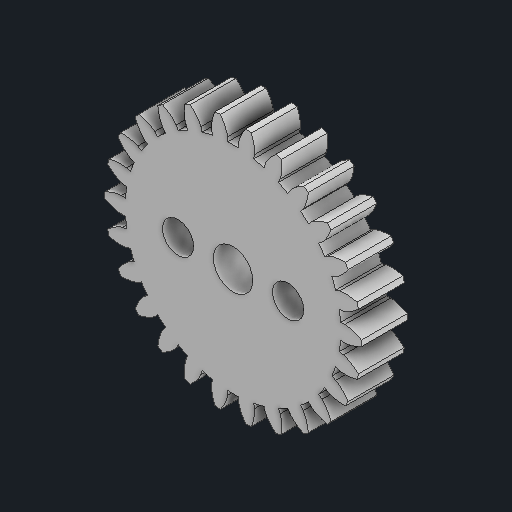
# Autodesk Inventor part: P2-02 Left driven gear 26 teeth
Saved by Autodesk Inventor 2027.1 (Build 311270010, 270A)
## iProperties
Created: 2026-10-21
Part Number: P2-02 Left driven gear 26 teeth
Material: Generic
Document SubType Name: Modeling
Designer: anshi
Mass: 2.32576 g
Surface Area: 20.344 cm^2
Volume: 2.32576 cm^3
Density: 1 g/cm^3
Appearance: Default
Author: anshi
Autodesk Inventor part; units mm, degrees
ref_plane "YZ Plane" through (0, 0, 0) normal (1, 0, 0) x (0, 1, 0)
ref_plane "XZ Plane" through (0, 0, 0) normal (0, 1, 0) x (-1, 0, 0)
ref_plane "XY Plane" through (0, 0, 0) normal (0, 0, 1) x (1, 0, 0)
sketch "Dimensioned base profile" plane through (0, 0, 0) normal (0, 0, 1) x (1, 0, 0)
  line L0 (11.72, -0.8391) -> (12.1848, -0.8724)
  spline S0 degree 4 poles (12.1848, -0.8724) (12.1929, -0.8729) (12.2327, -0.8739) (12.2995, -0.8712) (12.4119, -0.8604) (12.5297, -0.8434) (12.6734, -0.8161) (12.8414, -0.7759) (13.033, -0.7206) (13.338, -0.6171) (13.6097, -0.5031) (13.8321, -0.3954) (13.9966, -0.308) knots 0 0 0 0 0 0.103858 0.165063 0.236355 0.316365 0.404189 0.499163 0.600773 0.708602 1 1 1 1 1
  arc A0 (13.9966, -0.308) -> (13.9966, 0.308) centre (0, 0) ccw
  spline S1 degree 4 poles (13.9966, 0.308) (13.8319, 0.3954) (13.6094, 0.503) (13.3375, 0.6169) (13.0324, 0.7203) (12.8406, 0.7756) (12.6726, 0.8157) (12.5289, 0.8431) (12.4112, 0.8601) (12.299, 0.871) (12.2325, 0.8737) (12.1928, 0.8729) (12.1848, 0.8724) knots 0 0 0 0 0 0.291573 0.399464 0.501128 0.596147 0.684003 0.76403 0.835317 0.896484 1 1 1 1 1
  line L1 (12.1848, 0.8724) -> (11.72, 0.8391)
  arc A1 (11.72, 0.8391) -> (11.5802, 1.9901) centre (0, 0) ccw
  line L2 (11.5802, 1.9901) -> (12.0395, 2.069)
  spline S2 degree 4 poles (12.0395, 2.069) (12.0476, 2.0703) (12.0864, 2.079) (12.1506, 2.0976) (12.2571, 2.135) (12.3674, 2.1797) (12.5004, 2.2407) (12.6539, 2.3199) (12.8267, 2.4194) (13.0981, 2.5929) (13.3346, 2.7686) (13.5248, 2.9263) (13.6636, 3.0505) knots 0 0 0 0 0 0.103855 0.165058 0.23635 0.316361 0.404186 0.499161 0.600771 0.708601 1 1 1 1 1
  arc A2 (13.6636, 3.0505) -> (13.5162, 3.6487) centre (0, 0) ccw
  spline S3 degree 4 poles (13.5162, 3.6487) (13.3348, 3.6939) (13.0921, 3.7449) (12.8, 3.7902) (12.4781, 3.8174) (12.2784, 3.8251) (12.1055, 3.8238) (11.9595, 3.816) (11.8415, 3.8045) (11.7309, 3.7884) (11.6666, 3.7754) (11.6289, 3.7653) (11.622, 3.763) knots 0 0 0 0 0 0.29244 0.40063 0.502549 0.597769 0.685759 0.765834 0.837054 0.897986 1 1 1 1 1
  line L3 (11.622, 3.763) -> (11.1786, 3.6195)
  arc A3 (11.1786, 3.6195) -> (10.7675, 4.7036) centre (0, 0) ccw
  line L4 (10.7675, 4.7036) -> (11.1945, 4.8901)
  spline S4 degree 4 poles (11.1945, 4.8901) (11.202, 4.8933) (11.2377, 4.911) (11.2956, 4.9444) (11.3901, 5.0061) (11.4864, 5.0759) (11.601, 5.167) (11.7311, 5.2806) (11.8751, 5.4186) (12.097, 5.6521) (12.2846, 5.8792) (12.4315, 6.0779) (12.5365, 6.2318) knots 0 0 0 0 0 0.103853 0.165057 0.236348 0.316359 0.404183 0.499157 0.600768 0.708598 1 1 1 1 1
  arc A4 (12.5365, 6.2318) -> (12.2502, 6.7773) centre (0, 0) ccw
  spline S5 degree 4 poles (12.2502, 6.7773) (12.0633, 6.7779) (11.8155, 6.7695) (11.521, 6.7437) (11.202, 6.6932) (11.0062, 6.6529) (10.8386, 6.6104) (10.6987, 6.5678) (10.5869, 6.5284) (10.4833, 6.4861) (10.424, 6.458) (10.3898, 6.4391) (10.3837, 6.435) knots 0 0 0 0 0 0.292402 0.400578 0.502484 0.597694 0.685676 0.765748 0.836972 0.89792 1 1 1 1 1
  line L5 (10.3837, 6.435) -> (9.9876, 6.1895)
  arc A5 (9.9876, 6.1895) -> (9.329, 7.1437) centre (0, 0) ccw
  line L6 (9.329, 7.1437) -> (9.699, 7.427)
  spline S6 degree 4 poles (9.699, 7.427) (9.7055, 7.4319) (9.7358, 7.4576) (9.784, 7.5039) (9.861, 7.5865) (9.9379, 7.6773) (10.0273, 7.7932) (10.1264, 7.9346) (10.2332, 8.1031) (10.3928, 8.3828) (10.5206, 8.6483) (10.6157, 8.8764) (10.6809, 9.0509) knots 0 0 0 0 0 0.103839 0.165041 0.236333 0.316345 0.40417 0.499146 0.600759 0.708592 1 1 1 1 1
  arc A6 (10.6809, 9.0509) -> (10.2724, 9.512) centre (0, 0) ccw
  spline S7 degree 4 poles (10.2724, 9.512) (10.0908, 9.4678) (9.8525, 9.4003) (9.573, 9.3046) (9.2755, 9.1792) (9.0952, 9.0932) (8.9428, 9.0117) (8.8171, 8.9369) (8.7179, 8.8719) (8.6273, 8.8061) (8.5762, 8.7647) (8.5473, 8.7382) (8.542, 8.733) knots 0 0 0 0 0 0.292256 0.400384 0.502252 0.597434 0.685401 0.765472 0.836714 0.897704 1 1 1 1 1
  line L7 (8.542, 8.733) -> (8.2161, 8.3999)
  arc A7 (8.2161, 8.3999) -> (7.3483, 9.1687) centre (0, 0) ccw
  line L8 (7.3483, 9.1687) -> (7.6397, 9.5323)
  spline S8 degree 4 poles (7.6397, 9.5323) (7.6448, 9.5387) (7.6682, 9.5709) (7.7039, 9.6274) (7.7589, 9.726) (7.8118, 9.8326) (7.8709, 9.9664) (7.9333, 10.1275) (7.9966, 10.3166) (8.0847, 10.6264) (8.1452, 10.9148) (8.1829, 11.1589) (8.2045, 11.344) knots 0 0 0 0 0 0.10386 0.165065 0.236357 0.316368 0.404192 0.499165 0.600774 0.708603 1 1 1 1 1
  arc A8 (8.2045, 11.344) -> (7.6975, 11.694) centre (0, 0) ccw
  spline S9 degree 4 poles (7.6975, 11.694) (7.5314, 11.6077) (7.3155, 11.4853) (7.0663, 11.3257) (6.8069, 11.1329) (6.6521, 11.0063) (6.5234, 10.8908) (6.4193, 10.7881) (6.3388, 10.7012) (6.2671, 10.6156) (6.2279, 10.563) (6.2071, 10.5302) (6.2038, 10.5235) knots 0 0 0 0 0 0.292519 0.400726 0.502651 0.597866 0.685837 0.765878 0.83705 0.897921 1 1 1 1 1
  line L9 (6.2038, 10.5235) -> (5.9672, 10.122)
  arc A9 (5.9672, 10.122) -> (4.9405, 10.6608) centre (0, 0) ccw
  line L10 (4.9405, 10.6608) -> (5.1365, 11.0837)
  spline S10 degree 4 poles (5.1365, 11.0837) (5.14, 11.091) (5.1549, 11.1279) (5.1761, 11.1913) (5.2059, 11.3002) (5.2317, 11.4163) (5.2571, 11.5605) (5.2791, 11.7317) (5.2954, 11.9305) (5.3067, 12.2524) (5.2965, 12.5469) (5.2747, 12.793) (5.2513, 12.9778) knots 0 0 0 0 0 0.103856 0.16506 0.236352 0.316363 0.404186 0.499161 0.60077 0.7086 1 1 1 1 1
  arc A10 (5.2513, 12.9778) -> (4.6753, 13.1963) centre (0, 0) ccw
  spline S11 degree 4 poles (4.6753, 13.1963) (4.5348, 13.0731) (4.3548, 12.9029) (4.1513, 12.6887) (3.9458, 12.4397) (3.8259, 12.2799) (3.7287, 12.137) (3.6521, 12.0123) (3.5946, 11.9085) (3.5452, 11.8079) (3.5195, 11.747) (3.5067, 11.7098) (3.5051, 11.7023) knots 0 0 0 0 0 0.292105 0.400173 0.501984 0.597113 0.685035 0.765074 0.836305 0.897322 1 1 1 1 1
  line L11 (3.5051, 11.7023) -> (3.3714, 11.2559)
  arc A11 (3.3714, 11.2559) -> (2.2457, 11.5334) centre (0, 0) ccw
  line L12 (2.2457, 11.5334) -> (2.3347, 11.9908)
  spline S12 degree 4 poles (2.3347, 11.9908) (2.3363, 11.9988) (2.342, 12.0382) (2.3474, 12.1048) (2.3502, 12.2177) (2.3475, 12.3366) (2.3377, 12.4826) (2.318, 12.6542) (2.2863, 12.8511) (2.2203, 13.1664) (2.1399, 13.4498) (2.0598, 13.6836) (1.9929, 13.8574) knots 0 0 0 0 0 0.103856 0.16506 0.236352 0.316364 0.404188 0.499162 0.600772 0.708602 1 1 1 1 1
  arc A12 (1.9929, 13.8574) -> (1.3813, 13.9317) centre (0, 0) ccw
  spline S13 degree 4 poles (1.3813, 13.9317) (1.2743, 13.7784) (1.1401, 13.57) (0.9936, 13.3133) (0.8535, 13.0223) (0.7753, 12.8384) (0.715, 12.6764) (0.6705, 12.5371) (0.6396, 12.4225) (0.6158, 12.3131) (0.6056, 12.2478) (0.6024, 12.2088) (0.6027, 12.2011) knots 0 0 0 0 0 0.292181 0.400272 0.502099 0.597236 0.685158 0.765186 0.836392 0.89737 1 1 1 1 1
  line L13 (0.6027, 12.2011) -> (0.5797, 11.7357)
  arc A13 (0.5797, 11.7357) -> (-0.5797, 11.7357) centre (0, 0) ccw
  line L14 (-0.5797, 11.7357) -> (-0.6027, 12.2011)
  spline S14 degree 4 poles (-0.6027, 12.2011) (-0.6031, 12.2093) (-0.607, 12.2489) (-0.6177, 12.3148) (-0.642, 12.4251) (-0.6731, 12.5399) (-0.7176, 12.6794) (-0.7777, 12.8413) (-0.8557, 13.0248) (-0.9952, 13.3151) (-1.1411, 13.5711) (-1.2747, 13.7789) (-1.3813, 13.9317) knots 0 0 0 0 0 0.103856 0.165061 0.236354 0.316365 0.40419 0.499164 0.600774 0.708603 1 1 1 1 1
  arc A14 (-1.3813, 13.9317) -> (-1.9929, 13.8574) centre (0, 0) ccw
  spline S15 degree 4 poles (-1.9929, 13.8574) (-2.06, 13.6834) (-2.1402, 13.4495) (-2.2208, 13.1658) (-2.2871, 12.8503) (-2.3189, 12.6533) (-2.3386, 12.4817) (-2.3485, 12.3357) (-2.3511, 12.2168) (-2.3482, 12.1042) (-2.3426, 12.0378) (-2.3367, 11.9986) (-2.3347, 11.9908) knots 0 0 0 0 0 0.291613 0.399514 0.501182 0.596199 0.684048 0.764063 0.835332 0.896479 1 1 1 1 1
  line L15 (-2.3347, 11.9908) -> (-2.2457, 11.5334)
  arc A15 (-2.2457, 11.5334) -> (-3.3714, 11.2559) centre (0, 0) ccw
  line L16 (-3.3714, 11.2559) -> (-3.5051, 11.7023)
  spline S16 degree 4 poles (-3.5051, 11.7023) (-3.5075, 11.7101) (-3.5208, 11.7476) (-3.547, 11.8091) (-3.597, 11.9103) (-3.6546, 12.0144) (-3.7312, 12.1391) (-3.8283, 12.2819) (-3.948, 12.4415) (-4.1529, 12.69) (-4.3557, 12.9036) (-4.5352, 13.0734) (-4.6753, 13.1963) knots 0 0 0 0 0 0.103828 0.165032 0.236326 0.31634 0.404168 0.499146 0.60076 0.708593 1 1 1 1 1
  arc A16 (-4.6753, 13.1963) -> (-5.2513, 12.9778) centre (0, 0) ccw
  spline S17 degree 4 poles (-5.2513, 12.9778) (-5.2747, 12.7929) (-5.2967, 12.5466) (-5.307, 12.252) (-5.2958, 11.93) (-5.2796, 11.7311) (-5.2576, 11.5598) (-5.2322, 11.4156) (-5.2063, 11.2996) (-5.1765, 11.1908) (-5.1552, 11.1276) (-5.1402, 11.0908) (-5.1365, 11.0837) knots 0 0 0 0 0 0.291525 0.399396 0.501039 0.596037 0.683875 0.763887 0.835165 0.896335 1 1 1 1 1
  line L17 (-5.1365, 11.0837) -> (-4.9405, 10.6608)
  arc A17 (-4.9405, 10.6608) -> (-5.9672, 10.122) centre (0, 0) ccw
  line L18 (-5.9672, 10.122) -> (-6.2038, 10.5235)
  spline S18 degree 4 poles (-6.2038, 10.5235) (-6.2081, 10.5303) (-6.23, 10.5636) (-6.2702, 10.6169) (-6.3429, 10.7032) (-6.4238, 10.7904) (-6.528, 10.8931) (-6.6565, 11.0086) (-6.8108, 11.1349) (-7.0692, 11.3272) (-7.3172, 11.4862) (-7.5321, 11.6081) (-7.6975, 11.694) knots 0 0 0 0 0 0.103756 0.164954 0.236249 0.316269 0.404104 0.499092 0.600717 0.708562 1 1 1 1 1
  arc A18 (-7.6975, 11.694) -> (-8.2045, 11.344) centre (0, 0) ccw
  spline S19 degree 4 poles (-8.2045, 11.344) (-8.1829, 11.159) (-8.1452, 10.9148) (-8.0845, 10.6265) (-7.9965, 10.3167) (-7.9331, 10.1276) (-7.8707, 9.9665) (-7.8116, 9.8327) (-7.7587, 9.7261) (-7.7038, 9.6275) (-7.6681, 9.571) (-7.6447, 9.5387) (-7.6397, 9.5323) knots 0 0 0 0 0 0.291401 0.399232 0.500844 0.595821 0.683648 0.763661 0.834955 0.89616 1 1 1 1 1
  line L19 (-7.6397, 9.5323) -> (-7.3483, 9.1687)
  arc A19 (-7.3483, 9.1687) -> (-8.2161, 8.3999) centre (0, 0) ccw
  line L20 (-8.2161, 8.3999) -> (-8.542, 8.733)
  spline S20 degree 4 poles (-8.542, 8.733) (-8.5478, 8.7384) (-8.577, 8.7654) (-8.6288, 8.8074) (-8.7201, 8.8737) (-8.8195, 8.939) (-8.9452, 9.0138) (-9.0976, 9.0952) (-9.2777, 9.181) (-9.5745, 9.3059) (-9.8534, 9.4011) (-10.0913, 9.4682) (-10.2724, 9.512) knots 0 0 0 0 0 0.103609 0.164795 0.236092 0.31612 0.403972 0.498979 0.600626 0.708496 1 1 1 1 1
  arc A20 (-10.2724, 9.512) -> (-10.6809, 9.0509) centre (0, 0) ccw
  spline S21 degree 4 poles (-10.6809, 9.0509) (-10.6154, 8.8764) (-10.5201, 8.6484) (-10.3919, 8.383) (-10.232, 8.1033) (-10.125, 7.9349) (-10.0259, 7.7934) (-9.9364, 7.6776) (-9.8597, 7.5868) (-9.783, 7.5043) (-9.7352, 7.4579) (-9.7049, 7.4322) (-9.699, 7.427) knots 0 0 0 0 0 0.29159 0.399491 0.501165 0.596196 0.684064 0.764102 0.835397 0.896565 1 1 1 1 1
  line L21 (-9.699, 7.427) -> (-9.329, 7.1437)
  arc A21 (-9.329, 7.1437) -> (-9.9876, 6.1895) centre (0, 0) ccw
  line L22 (-9.9876, 6.1895) -> (-10.3837, 6.435)
  spline S22 degree 4 poles (-10.3837, 6.435) (-10.3906, 6.4385) (-10.4254, 6.4575) (-10.4855, 6.4856) (-10.5898, 6.5279) (-10.7019, 6.5674) (-10.8419, 6.61) (-11.0093, 6.6526) (-11.2047, 6.6929) (-11.523, 6.7435) (-11.8167, 6.7694) (-12.0638, 6.7779) (-12.2502, 6.7773) knots 0 0 0 0 0 0.103137 0.164277 0.235571 0.315627 0.403525 0.498595 0.600316 0.708269 1 1 1 1 1
  arc A22 (-12.2502, 6.7773) -> (-12.5365, 6.2318) centre (0, 0) ccw
  spline S23 degree 4 poles (-12.5365, 6.2318) (-12.4309, 6.0779) (-12.2834, 5.8792) (-12.095, 5.652) (-11.8724, 5.4186) (-11.728, 5.2805) (-11.5978, 5.1669) (-11.4833, 5.0759) (-11.3872, 5.0062) (-11.2934, 4.9446) (-11.2365, 4.9113) (-11.2011, 4.8935) (-11.1945, 4.8901) knots 0 0 0 0 0 0.292048 0.40011 0.501925 0.59707 0.68502 0.765098 0.836378 0.89745 1 1 1 1 1
  line L23 (-11.1945, 4.8901) -> (-10.7675, 4.7036)
  arc A23 (-10.7675, 4.7036) -> (-11.1786, 3.6195) centre (0, 0) ccw
  line L24 (-11.1786, 3.6195) -> (-11.622, 3.763)
  spline S24 degree 4 poles (-11.622, 3.763) (-11.6296, 3.7651) (-11.6679, 3.7754) (-11.7331, 3.7884) (-11.8446, 3.8047) (-11.9629, 3.8163) (-12.1091, 3.8241) (-12.2818, 3.8254) (-12.4812, 3.8177) (-12.8022, 3.7904) (-13.0935, 3.7451) (-13.3354, 3.694) (-13.5162, 3.6487) knots 0 0 0 0 0 0.103381 0.164541 0.235833 0.315872 0.403744 0.498781 0.600465 0.708377 1 1 1 1 1
  arc A24 (-13.5162, 3.6487) -> (-13.6636, 3.0505) centre (0, 0) ccw
  spline S25 degree 4 poles (-13.6636, 3.0505) (-13.5235, 2.9264) (-13.3318, 2.7688) (-13.0935, 2.5934) (-12.8205, 2.4201) (-12.6469, 2.3206) (-12.4932, 2.2415) (-12.3601, 2.1805) (-12.2506, 2.1358) (-12.1457, 2.0987) (-12.0839, 2.0799) (-12.0456, 2.0711) (-12.0395, 2.069) knots 0 0 0 0 0 0.29301 0.401412 0.503527 0.598921 0.687053 0.767228 0.838488 0.899369 1 1 1 1 1
  line L25 (-12.0395, 2.069) -> (-11.5802, 1.9901)
  arc A25 (-11.5802, 1.9901) -> (-11.72, 0.8391) centre (0, 0) ccw
  line L26 (-11.72, 0.8391) -> (-12.1848, 0.8724)
  spline S26 degree 4 poles (-12.1848, 0.8724) (-12.1924, 0.872) (-12.232, 0.8727) (-12.2981, 0.8694) (-12.41, 0.8584) (-12.5275, 0.8413) (-12.6713, 0.8139) (-12.8393, 0.7738) (-13.0312, 0.7188) (-13.3366, 0.6157) (-13.6088, 0.5023) (-13.8317, 0.3951) (-13.9966, 0.308) knots 0 0 0 0 0 0.102877 0.163993 0.235287 0.315358 0.403282 0.498387 0.600148 0.708146 1 1 1 1 1
  arc A26 (-13.9966, 0.308) -> (-13.9966, -0.308) centre (0, 0) ccw
  spline S27 degree 4 poles (-13.9966, -0.308) (-13.8317, -0.3957) (-13.6089, -0.5037) (-13.3367, -0.618) (-13.0313, -0.7219) (-12.8394, -0.7774) (-12.6714, -0.8176) (-12.5276, -0.845) (-12.41, -0.8619) (-12.2981, -0.8726) (-12.232, -0.8748) (-12.1924, -0.8738) (-12.1848, -0.8724) knots 0 0 0 0 0 0.291935 0.399947 0.50171 0.596805 0.68471 0.764755 0.836019 0.897109 1 1 1 1 1
  line L27 (-12.1848, -0.8724) -> (-11.72, -0.8391)
  arc A27 (-11.72, -0.8391) -> (-11.5802, -1.9901) centre (0, 0) ccw
  line L28 (-11.5802, -1.9901) -> (-12.0395, -2.069)
  spline S28 degree 4 poles (-12.0395, -2.069) (-12.0456, -2.0682) (-12.0839, -2.0767) (-12.1453, -2.0938) (-12.2499, -2.1304) (-12.3594, -2.1746) (-12.4924, -2.2357) (-12.6462, -2.3151) (-12.8199, -2.4152) (-13.0931, -2.5898) (-13.3316, -2.7667) (-13.5234, -2.9255) (-13.6636, -3.0505) knots 0 0 0 0 0 0.099567 0.1603 0.231502 0.311688 0.399892 0.49541 0.597697 0.706314 1 1 1 1 1
  arc A28 (-13.6636, -3.0505) -> (-13.5162, -3.6487) centre (0, 0) ccw
  spline S29 degree 4 poles (-13.5162, -3.6487) (-13.335, -3.6941) (-13.0927, -3.7454) (-12.8009, -3.7909) (-12.4793, -3.8184) (-12.2797, -3.8262) (-12.1069, -3.825) (-11.9607, -3.8171) (-11.8426, -3.8055) (-11.7316, -3.7892) (-11.6671, -3.776) (-11.6289, -3.7656) (-11.622, -3.763) knots 0 0 0 0 0 0.292124 0.400206 0.502033 0.597182 0.685129 0.765198 0.836462 0.897514 1 1 1 1 1
  line L29 (-11.622, -3.763) -> (-11.1786, -3.6195)
  arc A29 (-11.1786, -3.6195) -> (-10.7675, -4.7036) centre (0, 0) ccw
  line L30 (-10.7675, -4.7036) -> (-11.1945, -4.8901)
  spline S30 degree 4 poles (-11.1945, -4.8901) (-11.1997, -4.8899) (-11.2347, -4.9076) (-11.2888, -4.9379) (-11.3807, -4.998) (-11.4759, -5.0668) (-11.5905, -5.158) (-11.721, -5.272) (-11.8661, -5.411) (-12.0904, -5.6465) (-12.2806, -5.8758) (-12.4297, -6.0764) (-12.5365, -6.2318) knots 0 0 0 0 0 0.097235 0.157742 0.228919 0.309217 0.397635 0.493448 0.596096 0.705127 1 1 1 1 1
  arc A30 (-12.5365, -6.2318) -> (-12.2502, -6.7773) centre (0, 0) ccw
  spline S31 degree 4 poles (-12.2502, -6.7773) (-12.0633, -6.7778) (-11.8155, -6.7693) (-11.5211, -6.7433) (-11.2021, -6.6928) (-11.0063, -6.6524) (-10.8387, -6.6098) (-10.6987, -6.5673) (-10.5869, -6.5278) (-10.4834, -6.4856) (-10.4242, -6.4578) (-10.3897, -6.4387) (-10.3837, -6.435) knots 0 0 0 0 0 0.292473 0.400679 0.502616 0.597858 0.685873 0.765978 0.837236 0.898219 1 1 1 1 1
  line L31 (-10.3837, -6.435) -> (-9.9876, -6.1895)
  arc A31 (-9.9876, -6.1895) -> (-9.329, -7.1437) centre (0, 0) ccw
  line L32 (-9.329, -7.1437) -> (-9.699, -7.427)
  spline S32 degree 4 poles (-9.699, -7.427) (-9.7035, -7.4286) (-9.7332, -7.4541) (-9.7778, -7.4966) (-9.8524, -7.5768) (-9.9283, -7.6664) (-10.0178, -7.7823) (-10.1172, -7.9242) (-10.225, -8.0939) (-10.3868, -8.3761) (-10.517, -8.6442) (-10.6141, -8.8746) (-10.6809, -9.0509) knots 0 0 0 0 0 0.096717 0.157193 0.228382 0.308716 0.39719 0.493071 0.595795 0.704908 1 1 1 1 1
  arc A32 (-10.6809, -9.0509) -> (-10.2724, -9.512) centre (0, 0) ccw
  spline S33 degree 4 poles (-10.2724, -9.512) (-10.0909, -9.4678) (-9.8525, -9.4003) (-9.573, -9.3047) (-9.2756, -9.1793) (-9.0953, -9.0932) (-8.9428, -9.0118) (-8.8171, -8.937) (-8.7179, -8.8719) (-8.6272, -8.8061) (-8.5762, -8.7648) (-8.5472, -8.738) (-8.542, -8.733) knots 0 0 0 0 0 0.292271 0.400408 0.502287 0.597482 0.685466 0.765558 0.836826 0.89785 1 1 1 1 1
  line L33 (-8.542, -8.733) -> (-8.2161, -8.3999)
  arc A33 (-8.2161, -8.3999) -> (-7.3483, -9.1687) centre (0, 0) ccw
  line L34 (-7.3483, -9.1687) -> (-7.6397, -9.5323)
  spline S34 degree 4 poles (-7.6397, -9.5323) (-7.6434, -9.5341) (-7.666, -9.5662) (-7.6985, -9.6169) (-7.7513, -9.7121) (-7.8033, -9.817) (-7.8624, -9.951) (-7.9251, -10.1126) (-7.9894, -10.3034) (-8.0793, -10.6167) (-8.142, -10.9089) (-8.1815, -11.1563) (-8.2045, -11.344) knots 0 0 0 0 0 0.094912 0.155236 0.226419 0.306847 0.395489 0.491597 0.594595 0.70402 1 1 1 1 1
  arc A34 (-8.2045, -11.344) -> (-7.6975, -11.694) centre (0, 0) ccw
  spline S35 degree 4 poles (-7.6975, -11.694) (-7.5319, -11.6074) (-7.3166, -11.4845) (-7.0682, -11.3244) (-6.8095, -11.1312) (-6.655, -11.0044) (-6.5264, -10.8888) (-6.4223, -10.786) (-6.3415, -10.6992) (-6.2694, -10.6138) (-6.2297, -10.562) (-6.2079, -10.5291) (-6.2038, -10.5235) knots 0 0 0 0 0 0.292491 0.400708 0.502659 0.597917 0.685948 0.766067 0.837335 0.898317 1 1 1 1 1
  line L35 (-6.2038, -10.5235) -> (-5.9672, -10.122)
  arc A35 (-5.9672, -10.122) -> (-4.9405, -10.6608) centre (0, 0) ccw
  line L36 (-4.9405, -10.6608) -> (-5.1365, -11.0837)
  spline S36 degree 4 poles (-5.1365, -11.0837) (-5.139, -11.087) (-5.1533, -11.1234) (-5.1725, -11.1812) (-5.2011, -11.2865) (-5.2264, -11.4009) (-5.2518, -11.5452) (-5.274, -11.7171) (-5.2908, -11.9175) (-5.3033, -12.2428) (-5.2944, -12.541) (-5.2738, -12.7904) (-5.2513, -12.9778) knots 0 0 0 0 0 0.095662 0.156062 0.22726 0.30766 0.396238 0.492254 0.595137 0.704425 1 1 1 1 1
  arc A36 (-5.2513, -12.9778) -> (-4.6753, -13.1963) centre (0, 0) ccw
  spline S37 degree 4 poles (-4.6753, -13.1963) (-4.5351, -13.0726) (-4.3554, -12.9018) (-4.1523, -12.6869) (-3.9472, -12.4374) (-3.8275, -12.2773) (-3.7303, -12.1343) (-3.6538, -12.0096) (-3.5962, -11.906) (-3.5466, -11.8058) (-3.5207, -11.746) (-3.5074, -11.7089) (-3.5051, -11.7023) knots 0 0 0 0 0 0.292559 0.400798 0.502766 0.598035 0.686073 0.766193 0.837454 0.898421 1 1 1 1 1
  line L37 (-3.5051, -11.7023) -> (-3.3714, -11.2559)
  arc A37 (-3.3714, -11.2559) -> (-2.2457, -11.5334) centre (0, 0) ccw
  line L38 (-2.2457, -11.5334) -> (-2.3347, -11.9908)
  spline S38 degree 4 poles (-2.3347, -11.9908) (-2.336, -11.9943) (-2.3411, -12.0332) (-2.3456, -12.0931) (-2.3481, -12.2018) (-2.3452, -12.3188) (-2.3353, -12.4649) (-2.3158, -12.6372) (-2.2843, -12.836) (-2.2187, -13.1552) (-2.139, -13.443) (-2.0594, -13.6806) (-1.9929, -13.8574) knots 0 0 0 0 0 0.09468 0.155008 0.226212 0.30667 0.395344 0.491485 0.594514 0.703967 1 1 1 1 1
  arc A38 (-1.9929, -13.8574) -> (-1.3813, -13.9317) centre (0, 0) ccw
  spline S39 degree 4 poles (-1.3813, -13.9317) (-1.2749, -13.7779) (-1.1415, -13.5688) (-0.9959, -13.3114) (-0.8566, -13.0198) (-0.7788, -12.8356) (-0.7187, -12.6734) (-0.6743, -12.534) (-0.6431, -12.4198) (-0.6189, -12.3109) (-0.6078, -12.2469) (-0.6037, -12.2077) (-0.6027, -12.2011) knots 0 0 0 0 0 0.292751 0.40106 0.503092 0.598415 0.686495 0.76664 0.837902 0.898833 1 1 1 1 1
  line L39 (-0.6027, -12.2011) -> (-0.5797, -11.7357)
  arc A39 (-0.5797, -11.7357) -> (0.5797, -11.7357) centre (0, 0) ccw
  line L40 (0.5797, -11.7357) -> (0.6027, -12.2011)
  spline S40 degree 4 poles (0.6027, -12.2011) (0.6039, -12.2051) (0.6081, -12.244) (0.6191, -12.304) (0.6429, -12.4106) (0.674, -12.5237) (0.7185, -12.6632) (0.7785, -12.8257) (0.8564, -13.011) (0.9958, -13.3049) (1.1414, -13.5649) (1.2749, -13.7761) (1.3813, -13.9317) knots 0 0 0 0 0 0.095825 0.156263 0.227488 0.307903 0.396483 0.492487 0.595342 0.704587 1 1 1 1 1
  arc A40 (1.3813, -13.9317) -> (1.9929, -13.8574) centre (0, 0) ccw
  spline S41 degree 4 poles (1.9929, -13.8574) (2.0594, -13.683) (2.139, -13.4485) (2.2189, -13.1642) (2.2844, -12.8483) (2.3159, -12.651) (2.3355, -12.4793) (2.3453, -12.3333) (2.3481, -12.2147) (2.3456, -12.1027) (2.3408, -12.0372) (2.3354, -11.998) (2.3347, -11.9908) knots 0 0 0 0 0 0.292214 0.400336 0.502204 0.597394 0.685378 0.765476 0.836753 0.897793 1 1 1 1 1
  line L41 (2.3347, -11.9908) -> (2.2457, -11.5334)
  arc A41 (2.2457, -11.5334) -> (3.3714, -11.2559) centre (0, 0) ccw
  line L42 (3.3714, -11.2559) -> (3.5051, -11.7023)
  spline S42 degree 4 poles (3.5051, -11.7023) (3.508, -11.7081) (3.5214, -11.7451) (3.5475, -11.8041) (3.597, -11.9038) (3.6546, -12.0071) (3.7312, -12.1319) (3.8283, -12.275) (3.9479, -12.4353) (4.1528, -12.6854) (4.3557, -12.9008) (4.5352, -13.0722) (4.6753, -13.1963) knots 0 0 0 0 0 0.100642 0.161525 0.232786 0.312961 0.401093 0.496486 0.5986 0.706999 1 1 1 1 1
  arc A42 (4.6753, -13.1963) -> (5.2513, -12.9778) centre (0, 0) ccw
  spline S43 degree 4 poles (5.2513, -12.9778) (5.2743, -12.7927) (5.2956, -12.5463) (5.3053, -12.2514) (5.2935, -11.9292) (5.277, -11.7303) (5.2549, -11.559) (5.2295, -11.4148) (5.2038, -11.2989) (5.1744, -11.1904) (5.1538, -11.1275) (5.1391, -11.0908) (5.1365, -11.0837) knots 0 0 0 0 0 0.291886 0.399891 0.501658 0.596764 0.684687 0.764753 0.836039 0.897146 1 1 1 1 1
  line L43 (5.1365, -11.0837) -> (4.9405, -10.6608)
  arc A43 (4.9405, -10.6608) -> (5.9672, -10.122) centre (0, 0) ccw
  line L44 (5.9672, -10.122) -> (6.2038, -10.5235)
  spline S44 degree 4 poles (6.2038, -10.5235) (6.208, -10.5279) (6.2299, -10.5605) (6.2693, -10.611) (6.341, -10.6957) (6.4217, -10.7821) (6.5258, -10.8849) (6.6543, -11.0007) (6.8089, -11.1279) (7.0678, -11.322) (7.3164, -11.483) (7.5317, -11.6067) (7.6975, -11.694) knots 0 0 0 0 0 0.099963 0.160782 0.232039 0.312251 0.400449 0.49593 0.598149 0.706667 1 1 1 1 1
  arc A44 (7.6975, -11.694) -> (8.2045, -11.344) centre (0, 0) ccw
  spline S45 degree 4 poles (8.2045, -11.344) (8.1825, -11.1587) (8.1441, -10.9143) (8.0828, -10.6257) (7.9942, -10.3156) (7.9305, -10.1264) (7.868, -9.9653) (7.8089, -9.8314) (7.7562, -9.725) (7.7017, -9.6268) (7.6669, -9.5708) (7.6438, -9.5386) (7.6397, -9.5323) knots 0 0 0 0 0 0.291981 0.40002 0.501817 0.596949 0.684891 0.764967 0.836253 0.89734 1 1 1 1 1
  line L45 (7.6397, -9.5323) -> (7.3483, -9.1687)
  arc A45 (7.3483, -9.1687) -> (8.2161, -8.3999) centre (0, 0) ccw
  line L46 (8.2161, -8.3999) -> (8.542, -8.733)
  spline S46 degree 4 poles (8.542, -8.733) (8.5478, -8.7374) (8.577, -8.7641) (8.6285, -8.8051) (8.7193, -8.8709) (8.8186, -8.9359) (8.9443, -9.0107) (9.0967, -9.0922) (9.2769, -9.1784) (9.5739, -9.304) (9.8531, -9.3999) (10.0911, -9.4677) (10.2724, -9.512) knots 0 0 0 0 0 0.102355 0.163417 0.234705 0.314802 0.402776 0.497949 0.599793 0.707883 1 1 1 1 1
  arc A46 (10.2724, -9.512) -> (10.6809, -9.0509) centre (0, 0) ccw
  spline S47 degree 4 poles (10.6809, -9.0509) (10.6154, -8.8764) (10.5201, -8.6484) (10.3919, -8.3829) (10.232, -8.1033) (10.125, -7.9348) (10.0259, -7.7934) (9.9364, -7.6776) (9.8597, -7.5868) (9.783, -7.5042) (9.7352, -7.4579) (9.7049, -7.4322) (9.699, -7.427) knots 0 0 0 0 0 0.291601 0.399506 0.501184 0.596217 0.684087 0.764126 0.83542 0.896586 1 1 1 1 1
  line L47 (9.699, -7.427) -> (9.329, -7.1437)
  arc A47 (9.329, -7.1437) -> (9.9876, -6.1895) centre (0, 0) ccw
  line L48 (9.9876, -6.1895) -> (10.3837, -6.435)
  spline S48 degree 4 poles (10.3837, -6.435) (10.3904, -6.4375) (10.4251, -6.4564) (10.4848, -6.4836) (10.5885, -6.5256) (10.7005, -6.5649) (10.8405, -6.6075) (11.0079, -6.6502) (11.2035, -6.6908) (11.5221, -6.7419) (11.8162, -6.7684) (12.0636, -6.7774) (12.2502, -6.7773) knots 0 0 0 0 0 0.102019 0.163051 0.234338 0.314454 0.402463 0.49768 0.599576 0.707725 1 1 1 1 1
  arc A48 (12.2502, -6.7773) -> (12.5365, -6.2318) centre (0, 0) ccw
  spline S49 degree 4 poles (12.5365, -6.2318) (12.431, -6.0779) (12.2835, -5.8792) (12.0952, -5.6521) (11.8727, -5.4186) (11.7284, -5.2806) (11.5982, -5.167) (11.4837, -5.076) (11.3876, -5.0062) (11.2936, -4.9446) (11.2366, -4.9113) (11.2012, -4.8935) (11.1945, -4.8901) knots 0 0 0 0 0 0.291956 0.399985 0.501772 0.596893 0.684826 0.764895 0.836177 0.897268 1 1 1 1 1
  line L49 (11.1945, -4.8901) -> (10.7675, -4.7036)
  arc A49 (10.7675, -4.7036) -> (11.1786, -3.6195) centre (0, 0) ccw
  line L50 (11.1786, -3.6195) -> (11.622, -3.763)
  spline S50 degree 4 poles (11.622, -3.763) (11.6298, -3.7652) (11.6682, -3.7757) (11.7337, -3.7889) (11.8454, -3.8052) (11.9638, -3.8169) (12.1099, -3.8247) (12.2826, -3.8259) (12.4819, -3.8182) (12.8028, -3.7907) (13.0938, -3.7453) (13.3355, -3.6941) (13.5162, -3.6487) knots 0 0 0 0 0 0.103801 0.165007 0.236304 0.316323 0.404155 0.499137 0.600754 0.708591 1 1 1 1 1
  arc A50 (13.5162, -3.6487) -> (13.6636, -3.0505) centre (0, 0) ccw
  spline S51 degree 4 poles (13.6636, -3.0505) (13.5247, -2.9263) (13.3345, -2.7686) (13.0978, -2.593) (12.8264, -2.4195) (12.6535, -2.32) (12.5, -2.2408) (12.367, -2.1799) (12.2568, -2.1352) (12.1503, -2.0978) (12.0862, -2.0791) (12.0474, -2.0704) (12.0395, -2.069) knots 0 0 0 0 0 0.291475 0.399332 0.500967 0.595962 0.683803 0.763823 0.835115 0.896304 1 1 1 1 1
  line L51 (12.0395, -2.069) -> (11.5802, -1.9901)
  arc A51 (11.5802, -1.9901) -> (11.72, -0.8391) centre (0, 0) ccw
  circle A52 centre (0, 0) radius 2.15
  circle A53 centre (-6, 0) radius 1.7
  circle A54 centre (6, 0) radius 1.7
  point P0 (12.1981, -0.8729)
  point P1 (12.238, -0.8728)
  point P2 (12.3044, -0.8698)
  point P3 (12.397, -0.8611)
  point P4 (12.5155, -0.8445)
  point P5 (12.6592, -0.8175)
  point P6 (12.8273, -0.7777)
  point P7 (13.019, -0.7228)
  point P8 (13.2331, -0.6506)
  point P9 (13.4684, -0.5587)
  point P10 (13.7234, -0.4452)
  point P11 (13.7232, 0.4451)
  point P12 (13.468, 0.5586)
  point P13 (13.2325, 0.6503)
  point P14 (13.0183, 0.7226)
  point P15 (12.8266, 0.7774)
  point P16 (12.6584, 0.8172)
  point P17 (12.5147, 0.8442)
  point P18 (12.3963, 0.8609)
  point P19 (12.3037, 0.8695)
  point P20 (12.2375, 0.8727)
  point P21 (12.1978, 0.8728)
  point P22 (12.0525, 2.0717)
  point P23 (12.0912, 2.0813)
  point P24 (12.1549, 2.1002)
  point P25 (12.2428, 2.1307)
  point P26 (12.3539, 2.1752)
  point P27 (12.4869, 2.2359)
  point P28 (12.6407, 2.3147)
  point P29 (12.8136, 2.4139)
  point P30 (13.0042, 2.5353)
  point P31 (13.2107, 2.6808)
  point P32 (13.4312, 2.852)
  point P33 (13.2168, 3.7161)
  point P34 (12.941, 3.7649)
  point P35 (12.6897, 3.7975)
  point P36 (12.4639, 3.8162)
  point P37 (12.2642, 3.8235)
  point P38 (12.0912, 3.8218)
  point P39 (11.9453, 3.8137)
  point P40 (11.8266, 3.8016)
  point P41 (11.7353, 3.788)
  point P42 (11.671, 3.7755)
  point P43 (11.6336, 3.7664)
  point P44 (11.2066, 4.8958)
  point P45 (11.2418, 4.9143)
  point P46 (11.2992, 4.9479)
  point P47 (11.3772, 4.9986)
  point P48 (11.4744, 5.0684)
  point P49 (11.5891, 5.1591)
  point P50 (11.7195, 5.2725)
  point P51 (11.8637, 5.4101)
  point P52 (12.0197, 5.5736)
  point P53 (12.1853, 5.7643)
  point P54 (12.3584, 5.9833)
  point P55 (11.9435, 6.7713)
  point P56 (11.664, 6.7528)
  point P57 (11.4122, 6.7245)
  point P58 (11.1884, 6.6887)
  point P59 (10.9928, 6.648)
  point P60 (10.8252, 6.605)
  point P61 (10.6855, 6.5622)
  point P62 (10.5732, 6.522)
  point P63 (10.4877, 6.4868)
  point P64 (10.4283, 6.4591)
  point P65 (10.3941, 6.4412)
  point P66 (9.7092, 7.4354)
  point P67 (9.7391, 7.4619)
  point P68 (9.7867, 7.5082)
  point P69 (9.8503, 7.5761)
  point P70 (9.928, 7.6671)
  point P71 (10.0176, 7.7826)
  point P72 (10.1171, 7.9239)
  point P73 (10.2242, 8.0921)
  point P74 (10.3365, 8.2882)
  point P75 (10.4517, 8.513)
  point P76 (10.5673, 8.767)
  point P77 (9.9762, 9.4327)
  point P78 (9.7095, 9.3478)
  point P79 (9.472, 9.2599)
  point P80 (9.2635, 9.1715)
  point P81 (9.0834, 9.0852)
  point P82 (8.931, 9.0033)
  point P83 (8.8056, 8.9283)
  point P84 (8.7061, 8.8624)
  point P85 (8.6314, 8.8079)
  point P86 (8.5801, 8.7669)
  point P87 (8.5509, 8.7414)
  point P88 (7.6477, 9.543)
  point P89 (7.6703, 9.5758)
  point P90 (7.7055, 9.6322)
  point P91 (7.751, 9.7134)
  point P92 (7.8046, 9.8203)
  point P93 (7.864, 9.9539)
  point P94 (7.9268, 10.1149)
  point P95 (7.9905, 10.3038)
  point P96 (8.0527, 10.5211)
  point P97 (8.1107, 10.7669)
  point P98 (8.1622, 11.0412)
  point P99 (7.4282, 11.5463)
  point P100 (7.1888, 11.4002)
  point P101 (6.9787, 11.2581)
  point P102 (6.797, 11.1225)
  point P103 (6.6425, 10.9957)
  point P104 (6.514, 10.8798)
  point P105 (6.4102, 10.7769)
  point P106 (6.3296, 10.6891)
  point P107 (6.2706, 10.6182)
  point P108 (6.2313, 10.566)
  point P109 (6.21, 10.5341)
  point P110 (5.1417, 11.0959)
  point P111 (5.1558, 11.1332)
  point P112 (5.1765, 11.1963)
  point P113 (5.2012, 11.286)
  point P114 (5.2277, 11.4027)
  point P115 (5.2534, 11.5466)
  point P116 (5.2758, 11.718)
  point P117 (5.2925, 11.9167)
  point P118 (5.3008, 12.1425)
  point P119 (5.2984, 12.395)
  point P120 (5.2827, 12.6737)
  point P121 (4.4494, 12.9889)
  point P122 (4.2523, 12.7901)
  point P123 (4.0825, 12.6022)
  point P124 (3.9387, 12.4273)
  point P125 (3.8191, 12.2673)
  point P126 (3.7222, 12.1241)
  point P127 (3.646, 11.9994)
  point P128 (3.5887, 11.8947)
  point P129 (3.5481, 11.8114)
  point P130 (3.5222, 11.751)
  point P131 (3.5087, 11.7144)
  point P132 (2.3369, 12.0039)
  point P133 (2.3416, 12.0435)
  point P134 (2.3465, 12.1098)
  point P135 (2.3491, 12.2028)
  point P136 (2.3469, 12.3224)
  point P137 (2.3374, 12.4683)
  point P138 (2.3182, 12.6401)
  point P139 (2.2868, 12.837)
  point P140 (2.2409, 13.0582)
  point P141 (2.1781, 13.3028)
  point P142 (2.0961, 13.5697)
  point P143 (1.2115, 13.6762)
  point P144 (1.0675, 13.436)
  point P145 (0.9475, 13.2129)
  point P146 (0.8496, 13.0086)
  point P147 (0.7717, 12.8246)
  point P148 (0.7118, 12.6624)
  point P149 (0.6677, 12.523)
  point P150 (0.6372, 12.4077)
  point P151 (0.6178, 12.3172)
  point P152 (0.6073, 12.2524)
  point P153 (0.6032, 12.2137)
  point P154 (-0.6038, 12.2144)
  point P155 (-0.6087, 12.2539)
  point P156 (-0.6197, 12.3195)
  point P157 (-0.6395, 12.4104)
  point P158 (-0.6703, 12.526)
  point P159 (-0.7144, 12.6654)
  point P160 (-0.7742, 12.8275)
  point P161 (-0.8518, 13.0112)
  point P162 (-0.9493, 13.215)
  point P163 (-1.0688, 13.4375)
  point P164 (-1.2122, 13.677)
  point P165 (-2.0964, 13.5694)
  point P166 (-2.1785, 13.3023)
  point P167 (-2.2415, 13.0575)
  point P168 (-2.2876, 12.8361)
  point P169 (-2.3191, 12.6391)
  point P170 (-2.3383, 12.4674)
  point P171 (-2.3478, 12.3215)
  point P172 (-2.35, 12.2019)
  point P173 (-2.3472, 12.1091)
  point P174 (-2.3421, 12.043)
  point P175 (-2.3371, 12.0037)
  point P176 (-3.5094, 11.7149)
  point P177 (-3.5236, 11.7521)
  point P178 (-3.5501, 11.8131)
  point P179 (-3.591, 11.8966)
  point P180 (-3.6486, 12.0015)
  point P181 (-3.7248, 12.1263)
  point P182 (-3.8216, 12.2694)
  point P183 (-3.9409, 12.4292)
  point P184 (-4.0844, 12.6038)
  point P185 (-4.2536, 12.7912)
  point P186 (-4.4501, 12.9894)
  point P187 (-5.2828, 12.6735)
  point P188 (-5.2986, 12.3947)
  point P189 (-5.3012, 12.142)
  point P190 (-5.2929, 11.9161)
  point P191 (-5.2763, 11.7173)
  point P192 (-5.2539, 11.5459)
  point P193 (-5.2282, 11.402)
  point P194 (-5.2017, 11.2854)
  point P195 (-5.1768, 11.1958)
  point P196 (-5.1561, 11.1328)
  point P197 (-5.1418, 11.0957)
  point P198 (-6.211, 10.5345)
  point P199 (-6.2338, 10.5672)
  constraints: 104 end point, 104 point on circle, 55 centre point, 676 other
extrude "Thickness 5 mm" add sketch "Dimensioned base profile" along normal blind 5
sketch "M3 nut sockets AF5.7" plane through (0, 0, 0) normal (0, 0, 1) x (1, 0, 0)
  line L0 (-3.15, 1.6454) -> (-6, 3.2909)
  line L1 (-6, 3.2909) -> (-8.85, 1.6454)
  line L2 (-8.85, 1.6454) -> (-8.85, -1.6454)
  line L3 (-8.85, -1.6454) -> (-6, -3.2909)
  line L4 (-6, -3.2909) -> (-3.15, -1.6454)
  line L5 (-3.15, -1.6454) -> (-3.15, 1.6454)
  line L6 (8.85, 1.6454) -> (6, 3.2909)
  line L7 (6, 3.2909) -> (3.15, 1.6454)
  line L8 (3.15, 1.6454) -> (3.15, -1.6454)
  line L9 (3.15, -1.6454) -> (6, -3.2909)
  line L10 (6, -3.2909) -> (8.85, -1.6454)
  line L11 (8.85, -1.6454) -> (8.85, 1.6454)
  constraints: 24 end point
extrude "Nut sockets depth 2.4" cut sketch "M3 nut sockets AF5.7" along normal blind 2.4
equation "\"NominalThickness\" = 5"
equation "\"Module\" = 1"
body "Solid2"
